ESP8266 (Autodesk Fusion 360 design; units mm, degrees)
Autodesk Fusion 360 part; units mm, degrees
sketch "Sketch1" plane through (0, 0, 0) normal (0, 1, 0) x (1, 0, 0)
  line L0 (12.7, -24.05) -> (-12.7, -24.05)
  line L1 (-12.7, -24.05) -> (-12.7, 24.05)
  line L2 (-12.7, 24.05) -> (12.7, 24.05)
  line L3 (12.7, 24.05) -> (12.7, -24.05)
  circle A0 centre (10.3, -21.65) radius 1.4
  circle A1 centre (10.3, 21.65) radius 1.4
  circle A2 centre (-10.3, 21.65) radius 1.4
  circle A3 centre (-10.3, -21.65) radius 1.4
  line L4 (-13.45, 24.8) -> (13.45, 24.8)
  line L5 (13.45, 24.8) -> (13.45, -24.8)
  line L6 (13.45, -24.8) -> (-13.45, -24.8)
  line L7 (-13.45, -24.8) -> (-13.45, 24.8)
  line L8 (-13.45, 24.8) -> (13.45, -24.8) construction
  line L9 (13.45, 24.8) -> (-13.45, -24.8) construction
  dimension "d1" = 25.4
  dimension "d2" = 48.1
  dimension "d4" = 2.8
  dimension "d5" = 2.8
  dimension "d6" = 2.8
  dimension "d7" = 2.8
  dimension "d9" = 2.4
  dimension "d10" = 2.4
  dimension "d11" = 2.4
  dimension "d12" = 2.4
  dimension "d13" = 2.4
  dimension "d14" = 2.4
  dimension "d15" = 2.4
  dimension "d16" = 2.4
  dimension "d21" = 26.9
  dimension "d22" = 49.6
  dimension "d40" = 0.75
  dimension "d41" = 0.75
  constraint perpendicular L0 L1
  constraint parallel L0 L2
  constraint parallel L1 L3
  constraint horizontal L0
  constraint perpendicular L4 L5
  constraint parallel L4 L6
  constraint parallel L5 L7
  constraint horizontal L4
  constraint coincident L8 origin
  constraint coincident L9 origin
  measures "d1" distance of L1.end L2.end
  measures "d2" distance of L0.end L1.end
  measures "d4" diameter of A0
  measures "d5" diameter of A1
  measures "d6" diameter of A2
  measures "d7" diameter of A3
  measures "d9" distance of L0 A3.centre
  measures "d10" distance of L1 A3.centre
  measures "d11" distance of L3 A0.centre
  measures "d12" distance of L0 A0.centre
  measures "d13" distance of L3 A1.centre
  measures "d14" distance of L2 A1.centre
  measures "d15" distance of L2 A2.centre
  measures "d16" distance of L1 A2.centre
  measures "d21" distance of L5.end L6.end
  measures "d22" vertical distance of L4.end L5.end
  measures "d40" distance of L2 L4
  measures "d41" distance of L3 L5
extrude "Extrude1" add sketch "Sketch1" along normal blind 1.5 contours L0 L1 L2 L3
extrude "Extrude2" add sketch "Sketch1" along normal blind 5.5 contours A0 | A1 | A2 | A3
extrude "Extrude3" add sketch "Sketch1" along normal blind 7 contours L4 L5 L6 L7
sketch "Sketch2" plane through (0, 0, 24.8) normal (0, 0, 1) x (1, 0, 0)
  line L0 (-13.45, 0) -> (13.45, 0)
  line L1 (13.45, 0) -> (13.45, 7)
  line L2 (13.45, 7) -> (-13.45, 7)
  line L3 (-13.45, 7) -> (-13.45, 0)
  line L4 (3.975, 3.2502) -> (-3.975, 3.2502)
  line L5 (-3.975, 3.2502) -> (-3.975, 7.0002)
  line L6 (-3.975, 7.0002) -> (3.975, 7.0002)
  line L7 (3.975, 7.0002) -> (3.975, 3.2502)
  point P0 (0, 4.7502)
  dimension "d31" = 7.95
  dimension "d32" = 3.75
  constraint perpendicular L4 L5
  constraint parallel L4 L6
  constraint parallel L5 L7
  constraint horizontal L4
  measures "d31" distance of L5.end L6.end
  measures "d32" distance of L4.end L5.end
chamfer "Chamfer1" distance 0.5 angle 45 4 edges at (8.9947, 5.5, -21.1437) (-11.6053, 5.5, -21.1437) (-11.6053, 5.5, 22.1563) (8.9947, 5.5, 22.1563) tangent chain off
fillet "Fillet3" radius 2 4 edges at (12.7, 4.25, 24.05) (-12.7, 4.25, 24.05) (-12.7, 4.25, -24.05) (12.7, 4.25, -24.05)
fillet "Fillet4" radius 2 4 edges at (13.45, 3.5, -24.8) (-13.45, 3.5, -24.8) (-13.45, 3.5, 24.8) (13.45, 3.5, 24.8)
extrude "Extrude5" cut sketch "Sketch2" against normal up to surface (0.75 mm away) contours L2 L4 L5 L6 L7
chamfer "Chamfer2" distance 1.5 distance2 1.5 2 edges at (3.975, 3.2502, 24.425) (-3.975, 3.2502, 24.425) measured on face at (1.325, 3.2502, 24.55) measured on face at (-3.975, 4.5002, 24.55) tangent chain off
chamfer "Chamfer3" distance 0.25 angle 45 2 edges at (-3.975, 7, 24.425) (3.975, 7, 24.425) tangent chain off
named bodies: "ESP8266 Case"
